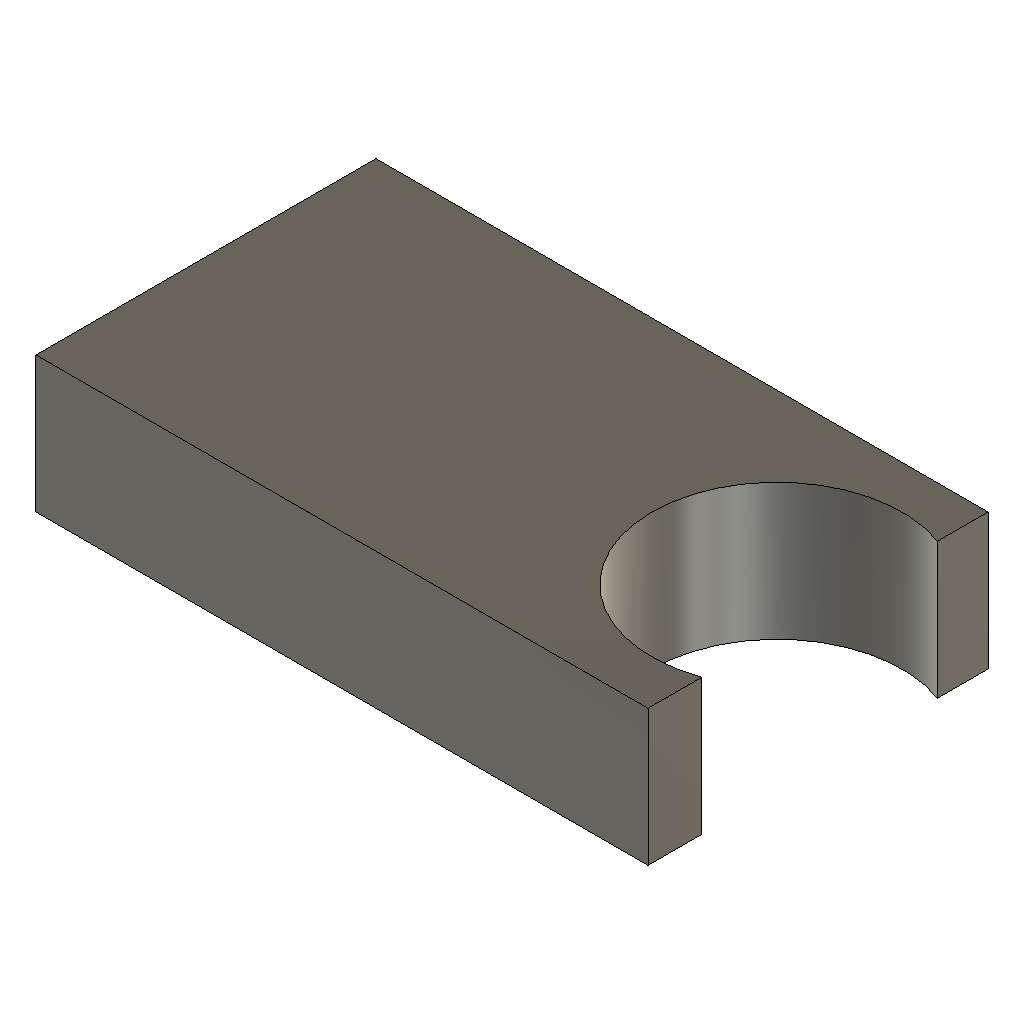
f2sc-test-combine-keep (Autodesk Fusion 360 design; units mm, degrees)
part number: 2026-11-27-15-54-18-897
Autodesk Fusion 360 part; units mm, degrees
sketch "Sketch1" plane through (0, 0, 0) normal (0, 0, 1) x (1, 0, 0)
  line L0 (-25, 25) -> (20, 25)
  line L1 (20, 25) -> (20, 50)
  line L2 (20, 50) -> (-25, 50)
  line L3 (-25, 50) -> (-25, 25)
  constraint horizontal L0
  constraint vertical L1
  constraint horizontal L2
  constraint vertical L3
extrude "Extrude1" add sketch "Sketch1" along normal blind 10 makes body 1
sketch "Sketch2" plane through (0, 0, 10) normal (0, 0, 1) x (-1, 0, 0)
  line L0 (25, -50) -> (25, -25)
  line L1 (25, -25) -> (-20, -25)
  line L2 (-20, -25) -> (-20, -50)
  line L3 (-20, -50) -> (25, -50)
  circle A0 centre (-16.8578, -37.6259) radius 9.211
extrude "Extrude2" add sketch "Sketch2" against normal blind 20 separate body contours L2 A0 picked at (-12.5969, -37.9947) makes body 2
combine "Combine1" operation cut target body 1 tool bodies 2 keep tools
hidden bodies 2
